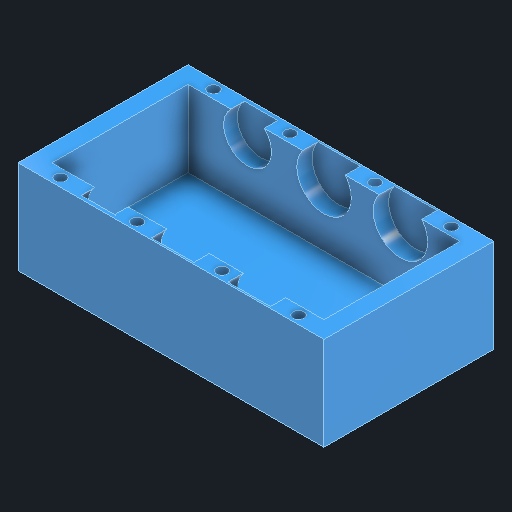
# Autodesk Inventor part: Carcaca_inferior
Saved by Autodesk Inventor 2027 (Build 310192000, 192)
## iProperties
Created: 2026-11-10
Part Number: Carcaca_inferior
Material: Genérico
Description: Carcaca inferior
Document SubType Name: Modeling
Designer: Bruno Madela
Mass: 365.216 g
Surface Area: 992.887 cm^2
Volume: 365.216 cm^3
Density: 1 g/cm^3
Appearance: Azul - Tinta de parede - Com brilho
Author: Bruno Madela
Autodesk Inventor part; units mm, degrees
sketch "Esboço1" plane through (0, 0, 0) normal (0, 1, 0) x (-1, 0, 0)
  line L0 (0, 100) -> (-180, 100)
  line L1 (-180, 100) -> (-180, 0)
  line L2 (-180, 0) -> (0, 0)
  line L3 (0, 0) -> (0, 100)
  constraints: 8 end point, 2 parallel, 1 horizontal, 1 perpendicular
extrude "Corpo externo 180x100x55" add sketch "Esboço1" along normal blind 55
ref_plane "Plano de trabalho1" through (0, 10, 0) normal (0, 1, 0) x (-1, 0, 0)
sketch "Esboço2" plane through (0, 10, 0) normal (0, 1, 0) x (-1, 0, 0)
  line L0 (-10, 90) -> (-170, 90)
  line L1 (-170, 90) -> (-170, 10)
  line L2 (-170, 10) -> (-10, 10)
  line L3 (-10, 10) -> (-10, 90)
  constraints: 8 end point, 2 parallel, 1 horizontal, 1 perpendicular
extrude "Cavidade interna 160x80x45" cut sketch "Esboço2" along normal blind 45
ref_plane "Plano de trabalho2" through (0, 0, 90) normal (0, 0, 1) x (1, 0, 0)
sketch "Esboço3" plane through (0, 0, 90) normal (0, 0, 1) x (1, 0, 0)
  circle A0 centre (45, 45) radius 14
  constraints: 1 centre point
extrude "Alojamento 6001 (frente)" cut sketch "Esboço3" along normal blind 8
sketch "Esboço4" plane through (0, 0, 90) normal (0, 0, 1) x (1, 0, 0)
  circle A0 centre (90, 45) radius 16
  circle A1 centre (135, 45) radius 16
  constraints: 2 centre point
extrude "Alojamentos 6002 (frente)" cut sketch "Esboço4" along normal blind 9
ref_plane "Plano de trabalho3" through (0, 0, 10) normal (0, 0, 1) x (1, 0, 0)
sketch "Esboço5" plane through (0, 0, 10) normal (0, 0, 1) x (1, 0, 0)
  circle A0 centre (45, 45) radius 14
  constraints: 1 centre point
extrude "Alojamento 6001 (fundo)" cut sketch "Esboço5" against normal blind 8
sketch "Esboço6" plane through (0, 0, 10) normal (0, 0, 1) x (1, 0, 0)
  circle A0 centre (90, 45) radius 16
  circle A1 centre (135, 45) radius 16
  constraints: 2 centre point
extrude "Alojamentos 6002 (fundo)" cut sketch "Esboço6" against normal blind 9
sketch "Esboço7" plane through (0, 0, 0) normal (0, 1, 0) x (-1, 0, 0)
  circle A0 centre (-20, 95) radius 3.25
  circle A1 centre (-20, 5) radius 3.25
  circle A2 centre (-65, 95) radius 3.25
  circle A3 centre (-65, 5) radius 3.25
  circle A4 centre (-115, 95) radius 3.25
  circle A5 centre (-115, 5) radius 3.25
  circle A6 centre (-160, 95) radius 3.25
  circle A7 centre (-160, 5) radius 3.25
  constraints: 8 centre point
extrude "Furos de passagem M6 (8x D6,5)" cut sketch "Esboço7" along normal blind 55
